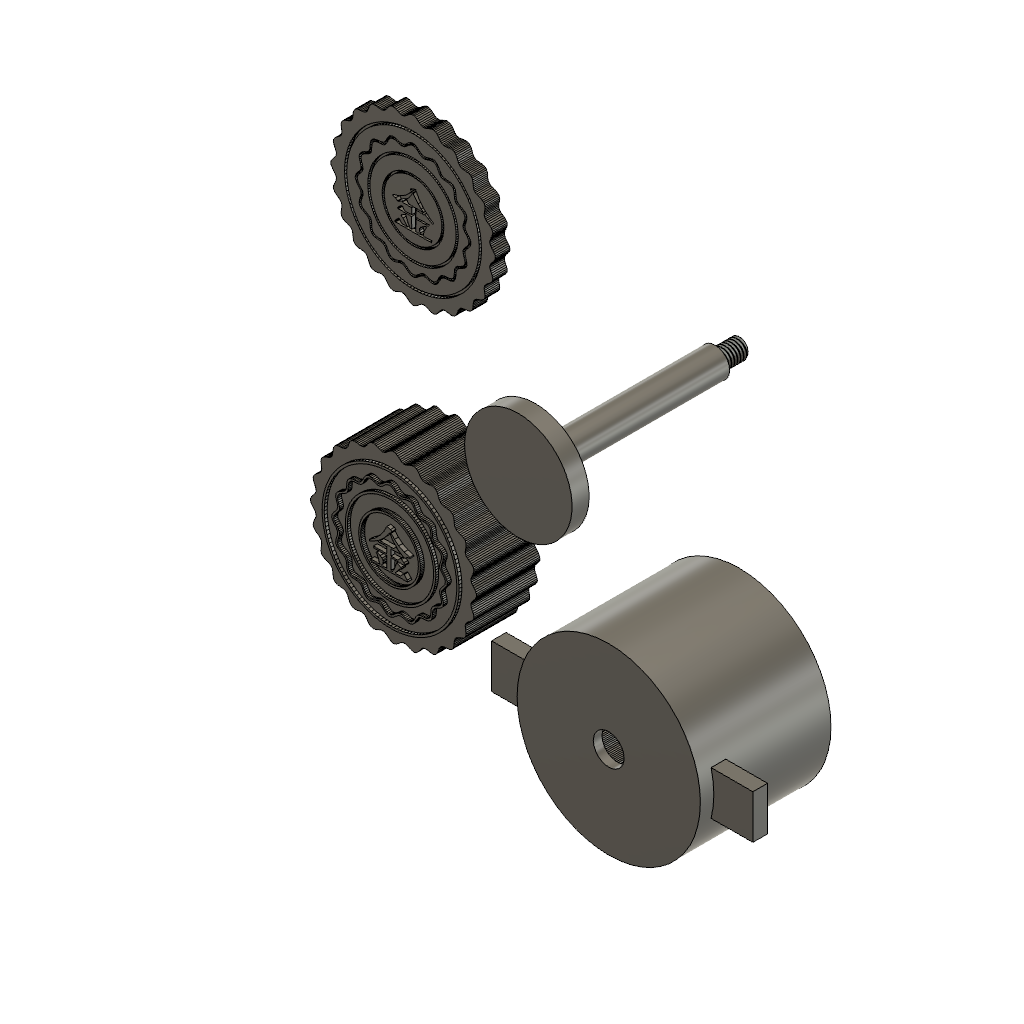
Mooncake-金-68mm-月饼与模具 (Autodesk Fusion 360 design; units mm, degrees)
part number: 2026-09-19-11-01-06-843
part number: 2026-09-19-11-01-06-994
part number: 2026-09-19-11-01-14-497
part number: 2026-09-19-11-01-14-514
part number: 2026-09-19-11-01-14-529
Autodesk Fusion 360 part; units mm, degrees
(part 1 of 5)
sketch "草图1" plane through (0, 0, 0) normal (0, 0, 1) x (1, 0, 0) in component "01_月饼_金_68mm"
  line L0 (34, 0) -> (33.9193, 0.5551)
  line L1 (33.9193, 0.5551) -> (33.6891, 1.1029)
  line L2 (33.6891, 1.1029) -> (33.3425, 1.638)
  line L3 (33.3425, 1.638) -> (32.9293, 2.1583)
  line L4 (32.9293, 2.1583) -> (32.5082, 2.6655)
  line L5 (32.5082, 2.6655) -> (32.1374, 3.1653)
  line L6 (32.1374, 3.1653) -> (31.866, 3.6659)
  line L7 (31.866, 3.6659) -> (31.7262, 4.1768)
  line L8 (31.7262, 4.1768) -> (31.7289, 4.7065)
  line L9 (31.7289, 4.7065) -> (31.8616, 5.2604)
  line L10 (31.8616, 5.2604) -> (32.0904, 5.839)
  line L11 (32.0904, 5.839) -> (32.3659, 6.438)
  line L12 (32.3659, 6.438) -> (32.6303, 7.0475)
  line L13 (32.6303, 7.0475) -> (32.8266, 7.6541)
  line L14 (32.8266, 7.6541) -> (32.9072, 8.2428)
  line L15 (32.9072, 8.2428) -> (32.8415, 8.7998)
  line L16 (32.8415, 8.7998) -> (32.6199, 9.3151)
  line L17 (32.6199, 9.3151) -> (32.2557, 9.7847)
  line L18 (32.2557, 9.7847) -> (31.7824, 10.2119)
  line L19 (31.7824, 10.2119) -> (31.2487, 10.6075)
  line L20 (31.2487, 10.6075) -> (30.7106, 10.9884)
  line L21 (30.7106, 10.9884) -> (30.2231, 11.3752)
  line L22 (30.2231, 11.3752) -> (29.8313, 11.7885)
  line L23 (29.8313, 11.7885) -> (29.5641, 12.2459)
  line L24 (29.5641, 12.2459) -> (29.4297, 12.7582)
  line L25 (29.4297, 12.7582) -> (29.4144, 13.3275)
  line L26 (29.4144, 13.3275) -> (29.4857, 13.9457)
  line L27 (29.4857, 13.9457) -> (29.5968, 14.5955)
  line L28 (29.5968, 14.5955) -> (29.6944, 15.2527)
  line L29 (29.6944, 15.2527) -> (29.727, 15.8894)
  line L30 (29.727, 15.8894) -> (29.6525, 16.479)
  line L31 (29.6525, 16.479) -> (29.4449, 17)
  line L32 (29.4449, 17) -> (29.0975, 17.4404)
  line L33 (29.0975, 17.4404) -> (28.6241, 17.7996)
  line L34 (28.6241, 17.7996) -> (28.0564, 18.0898)
  line L35 (28.0564, 18.0898) -> (27.4385, 18.3338)
  line L36 (27.4385, 18.3338) -> (26.8202, 18.5625)
  line L37 (26.8202, 18.5625) -> (26.2492, 18.8099)
  line L38 (26.2492, 18.8099) -> (25.7638, 19.1077)
  line L39 (25.7638, 19.1077) -> (25.3873, 19.4804)
  line L40 (25.3873, 19.4804) -> (25.1248, 19.9405)
  line L41 (25.1248, 19.9405) -> (24.9627, 20.4864)
  line L42 (24.9627, 20.4864) -> (24.8716, 21.102)
  line L43 (24.8716, 21.102) -> (24.8107, 21.7584)
  line L44 (24.8107, 21.7584) -> (24.7349, 22.4184)
  line L45 (24.7349, 22.4184) -> (24.6016, 23.0419)
  line L46 (24.6016, 23.0419) -> (24.3771, 23.5921)
  line L47 (24.3771, 23.5921) -> (24.0416, 24.0416)
  line L48 (24.0416, 24.0416) -> (23.5921, 24.3771)
  line L49 (23.5921, 24.3771) -> (23.0419, 24.6016)
  line L50 (23.0419, 24.6016) -> (22.4184, 24.7349)
  line L51 (22.4184, 24.7349) -> (21.7584, 24.8107)
  line L52 (21.7584, 24.8107) -> (21.102, 24.8716)
  line L53 (21.102, 24.8716) -> (20.4864, 24.9627)
  line L54 (20.4864, 24.9627) -> (19.9405, 25.1248)
  line L55 (19.9405, 25.1248) -> (19.4804, 25.3873)
  line L56 (19.4804, 25.3873) -> (19.1077, 25.7638)
  line L57 (19.1077, 25.7638) -> (18.8099, 26.2492)
  line L58 (18.8099, 26.2492) -> (18.5625, 26.8202)
  line L59 (18.5625, 26.8202) -> (18.3338, 27.4385)
  line L60 (18.3338, 27.4385) -> (18.0898, 28.0564)
  line L61 (18.0898, 28.0564) -> (17.7996, 28.6241)
  line L62 (17.7996, 28.6241) -> (17.4404, 29.0975)
  line L63 (17.4404, 29.0975) -> (17, 29.4449)
  line L64 (17, 29.4449) -> (16.479, 29.6525)
  line L65 (16.479, 29.6525) -> (15.8894, 29.727)
  line L66 (15.8894, 29.727) -> (15.2527, 29.6944)
  line L67 (15.2527, 29.6944) -> (14.5955, 29.5968)
  line L68 (14.5955, 29.5968) -> (13.9457, 29.4857)
  line L69 (13.9457, 29.4857) -> (13.3275, 29.4144)
  line L70 (13.3275, 29.4144) -> (12.7582, 29.4297)
  line L71 (12.7582, 29.4297) -> (12.2459, 29.5641)
  line L72 (12.2459, 29.5641) -> (11.7885, 29.8313)
  line L73 (11.7885, 29.8313) -> (11.3752, 30.2231)
  line L74 (11.3752, 30.2231) -> (10.9884, 30.7106)
  line L75 (10.9884, 30.7106) -> (10.6075, 31.2487)
  line L76 (10.6075, 31.2487) -> (10.2119, 31.7824)
  line L77 (10.2119, 31.7824) -> (9.7847, 32.2557)
  line L78 (9.7847, 32.2557) -> (9.3151, 32.6199)
  line L79 (9.3151, 32.6199) -> (8.7998, 32.8415)
  line L80 (8.7998, 32.8415) -> (8.2428, 32.9072)
  line L81 (8.2428, 32.9072) -> (7.6541, 32.8266)
  line L82 (7.6541, 32.8266) -> (7.0475, 32.6303)
  line L83 (7.0475, 32.6303) -> (6.438, 32.3659)
  line L84 (6.438, 32.3659) -> (5.839, 32.0904)
  line L85 (5.839, 32.0904) -> (5.2604, 31.8616)
  line L86 (5.2604, 31.8616) -> (4.7065, 31.7289)
  line L87 (4.7065, 31.7289) -> (4.1768, 31.7262)
  line L88 (4.1768, 31.7262) -> (3.6659, 31.866)
  line L89 (3.6659, 31.866) -> (3.1653, 32.1374)
  line L90 (3.1653, 32.1374) -> (2.6655, 32.5082)
  line L91 (2.6655, 32.5082) -> (2.1583, 32.9293)
  line L92 (2.1583, 32.9293) -> (1.638, 33.3425)
  line L93 (1.638, 33.3425) -> (1.1029, 33.6891)
  line L94 (1.1029, 33.6891) -> (0.5551, 33.9193)
  line L95 (0.5551, 33.9193) -> (0, 34)
  line L96 (0, 34) -> (-0.5551, 33.9193)
  line L97 (-0.5551, 33.9193) -> (-1.1029, 33.6891)
  line L98 (-1.1029, 33.6891) -> (-1.638, 33.3425)
  line L99 (-1.638, 33.3425) -> (-2.1583, 32.9293)
  line L100 (-2.1583, 32.9293) -> (-2.6655, 32.5082)
  line L101 (-2.6655, 32.5082) -> (-3.1653, 32.1374)
  line L102 (-3.1653, 32.1374) -> (-3.6659, 31.866)
  line L103 (-3.6659, 31.866) -> (-4.1768, 31.7262)
  line L104 (-4.1768, 31.7262) -> (-4.7065, 31.7289)
  line L105 (-4.7065, 31.7289) -> (-5.2604, 31.8616)
  line L106 (-5.2604, 31.8616) -> (-5.839, 32.0904)
  line L107 (-5.839, 32.0904) -> (-6.438, 32.3659)
  line L108 (-6.438, 32.3659) -> (-7.0475, 32.6303)
  line L109 (-7.0475, 32.6303) -> (-7.6541, 32.8266)
  line L110 (-7.6541, 32.8266) -> (-8.2428, 32.9072)
  line L111 (-8.2428, 32.9072) -> (-8.7998, 32.8415)
  line L112 (-8.7998, 32.8415) -> (-9.3151, 32.6199)
  line L113 (-9.3151, 32.6199) -> (-9.7847, 32.2557)
  line L114 (-9.7847, 32.2557) -> (-10.2119, 31.7824)
  line L115 (-10.2119, 31.7824) -> (-10.6075, 31.2487)
  line L116 (-10.6075, 31.2487) -> (-10.9884, 30.7106)
  line L117 (-10.9884, 30.7106) -> (-11.3752, 30.2231)
  line L118 (-11.3752, 30.2231) -> (-11.7885, 29.8313)
  line L119 (-11.7885, 29.8313) -> (-12.2459, 29.5641)
  line L120 (-12.2459, 29.5641) -> (-12.7582, 29.4297)
  line L121 (-12.7582, 29.4297) -> (-13.3275, 29.4144)
  line L122 (-13.3275, 29.4144) -> (-13.9457, 29.4857)
  line L123 (-13.9457, 29.4857) -> (-14.5955, 29.5968)
  line L124 (-14.5955, 29.5968) -> (-15.2527, 29.6944)
  line L125 (-15.2527, 29.6944) -> (-15.8894, 29.727)
  line L126 (-15.8894, 29.727) -> (-16.479, 29.6525)
  line L127 (-16.479, 29.6525) -> (-17, 29.4449)
  line L128 (-17, 29.4449) -> (-17.4404, 29.0975)
  line L129 (-17.4404, 29.0975) -> (-17.7996, 28.6241)
  line L130 (-17.7996, 28.6241) -> (-18.0898, 28.0564)
  line L131 (-18.0898, 28.0564) -> (-18.3338, 27.4385)
  line L132 (-18.3338, 27.4385) -> (-18.5625, 26.8202)
  line L133 (-18.5625, 26.8202) -> (-18.8099, 26.2492)
  line L134 (-18.8099, 26.2492) -> (-19.1077, 25.7638)
  line L135 (-19.1077, 25.7638) -> (-19.4804, 25.3873)
  line L136 (-19.4804, 25.3873) -> (-19.9405, 25.1248)
  line L137 (-19.9405, 25.1248) -> (-20.4864, 24.9627)
  line L138 (-20.4864, 24.9627) -> (-21.102, 24.8716)
  line L139 (-21.102, 24.8716) -> (-21.7584, 24.8107)
  line L140 (-21.7584, 24.8107) -> (-22.4184, 24.7349)
  line L141 (-22.4184, 24.7349) -> (-23.0419, 24.6016)
  line L142 (-23.0419, 24.6016) -> (-23.5921, 24.3771)
  line L143 (-23.5921, 24.3771) -> (-24.0416, 24.0416)
  line L144 (-24.0416, 24.0416) -> (-24.3771, 23.5921)
  line L145 (-24.3771, 23.5921) -> (-24.6016, 23.0419)
  line L146 (-24.6016, 23.0419) -> (-24.7349, 22.4184)
  line L147 (-24.7349, 22.4184) -> (-24.8107, 21.7584)
  line L148 (-24.8107, 21.7584) -> (-24.8716, 21.102)
  line L149 (-24.8716, 21.102) -> (-24.9627, 20.4864)
  line L150 (-24.9627, 20.4864) -> (-25.1248, 19.9405)
  line L151 (-25.1248, 19.9405) -> (-25.3873, 19.4804)
  line L152 (-25.3873, 19.4804) -> (-25.7638, 19.1077)
  line L153 (-25.7638, 19.1077) -> (-26.2492, 18.8099)
  line L154 (-26.2492, 18.8099) -> (-26.8202, 18.5625)
  line L155 (-26.8202, 18.5625) -> (-27.4385, 18.3338)
  line L156 (-27.4385, 18.3338) -> (-28.0564, 18.0898)
  line L157 (-28.0564, 18.0898) -> (-28.6241, 17.7996)
  line L158 (-28.6241, 17.7996) -> (-29.0975, 17.4404)
  line L159 (-29.0975, 17.4404) -> (-29.4449, 17)
  line L160 (-29.4449, 17) -> (-29.6525, 16.479)
  line L161 (-29.6525, 16.479) -> (-29.727, 15.8894)
  line L162 (-29.727, 15.8894) -> (-29.6944, 15.2527)
  line L163 (-29.6944, 15.2527) -> (-29.5968, 14.5955)
  line L164 (-29.5968, 14.5955) -> (-29.4857, 13.9457)
  line L165 (-29.4857, 13.9457) -> (-29.4144, 13.3275)
  line L166 (-29.4144, 13.3275) -> (-29.4297, 12.7582)
  line L167 (-29.4297, 12.7582) -> (-29.5641, 12.2459)
  line L168 (-29.5641, 12.2459) -> (-29.8313, 11.7885)
  line L169 (-29.8313, 11.7885) -> (-30.2231, 11.3752)
  line L170 (-30.2231, 11.3752) -> (-30.7106, 10.9884)
  line L171 (-30.7106, 10.9884) -> (-31.2487, 10.6075)
  line L172 (-31.2487, 10.6075) -> (-31.7824, 10.2119)
  line L173 (-31.7824, 10.2119) -> (-32.2557, 9.7847)
  line L174 (-32.2557, 9.7847) -> (-32.6199, 9.3151)
  line L175 (-32.6199, 9.3151) -> (-32.8415, 8.7998)
  line L176 (-32.8415, 8.7998) -> (-32.9072, 8.2428)
  line L177 (-32.9072, 8.2428) -> (-32.8266, 7.6541)
  line L178 (-32.8266, 7.6541) -> (-32.6303, 7.0475)
  line L179 (-32.6303, 7.0475) -> (-32.3659, 6.438)
  line L180 (-32.3659, 6.438) -> (-32.0904, 5.839)
  line L181 (-32.0904, 5.839) -> (-31.8616, 5.2604)
  line L182 (-31.8616, 5.2604) -> (-31.7289, 4.7065)
  line L183 (-31.7289, 4.7065) -> (-31.7262, 4.1768)
  line L184 (-31.7262, 4.1768) -> (-31.866, 3.6659)
  line L185 (-31.866, 3.6659) -> (-32.1374, 3.1653)
  line L186 (-32.1374, 3.1653) -> (-32.5082, 2.6655)
  line L187 (-32.5082, 2.6655) -> (-32.9293, 2.1583)
  line L188 (-32.9293, 2.1583) -> (-33.3425, 1.638)
  line L189 (-33.3425, 1.638) -> (-33.6891, 1.1029)
  line L190 (-33.6891, 1.1029) -> (-33.9193, 0.5551)
  line L191 (-33.9193, 0.5551) -> (-34, 0)
  line L192 (-34, 0) -> (-33.9193, -0.5551)
  line L193 (-33.9193, -0.5551) -> (-33.6891, -1.1029)
  line L194 (-33.6891, -1.1029) -> (-33.3425, -1.638)
  line L195 (-33.3425, -1.638) -> (-32.9293, -2.1583)
  line L196 (-32.9293, -2.1583) -> (-32.5082, -2.6655)
  line L197 (-32.5082, -2.6655) -> (-32.1374, -3.1653)
  line L198 (-32.1374, -3.1653) -> (-31.866, -3.6659)
  line L199 (-31.866, -3.6659) -> (-31.7262, -4.1768)
  line L200 (-31.7262, -4.1768) -> (-31.7289, -4.7065)
  line L201 (-31.7289, -4.7065) -> (-31.8616, -5.2604)
  line L202 (-31.8616, -5.2604) -> (-32.0904, -5.839)
  line L203 (-32.0904, -5.839) -> (-32.3659, -6.438)
  line L204 (-32.3659, -6.438) -> (-32.6303, -7.0475)
  line L205 (-32.6303, -7.0475) -> (-32.8266, -7.6541)
  line L206 (-32.8266, -7.6541) -> (-32.9072, -8.2428)
  line L207 (-32.9072, -8.2428) -> (-32.8415, -8.7998)
  line L208 (-32.8415, -8.7998) -> (-32.6199, -9.3151)
  line L209 (-32.6199, -9.3151) -> (-32.2557, -9.7847)
  line L210 (-32.2557, -9.7847) -> (-31.7824, -10.2119)
  line L211 (-31.7824, -10.2119) -> (-31.2487, -10.6075)
  line L212 (-31.2487, -10.6075) -> (-30.7106, -10.9884)
  line L213 (-30.7106, -10.9884) -> (-30.2231, -11.3752)
  line L214 (-30.2231, -11.3752) -> (-29.8313, -11.7885)
  line L215 (-29.8313, -11.7885) -> (-29.5641, -12.2459)
  line L216 (-29.5641, -12.2459) -> (-29.4297, -12.7582)
  line L217 (-29.4297, -12.7582) -> (-29.4144, -13.3275)
  line L218 (-29.4144, -13.3275) -> (-29.4857, -13.9457)
  line L219 (-29.4857, -13.9457) -> (-29.5968, -14.5955)
  line L220 (-29.5968, -14.5955) -> (-29.6944, -15.2527)
  line L221 (-29.6944, -15.2527) -> (-29.727, -15.8894)
  line L222 (-29.727, -15.8894) -> (-29.6525, -16.479)
  line L223 (-29.6525, -16.479) -> (-29.4449, -17)
  line L224 (-29.4449, -17) -> (-29.0975, -17.4404)
  line L225 (-29.0975, -17.4404) -> (-28.6241, -17.7996)
  line L226 (-28.6241, -17.7996) -> (-28.0564, -18.0898)
  line L227 (-28.0564, -18.0898) -> (-27.4385, -18.3338)
  line L228 (-27.4385, -18.3338) -> (-26.8202, -18.5625)
  line L229 (-26.8202, -18.5625) -> (-26.2492, -18.8099)
  line L230 (-26.2492, -18.8099) -> (-25.7638, -19.1077)
  line L231 (-25.7638, -19.1077) -> (-25.3873, -19.4804)
  line L232 (-25.3873, -19.4804) -> (-25.1248, -19.9405)
  line L233 (-25.1248, -19.9405) -> (-24.9627, -20.4864)
  line L234 (-24.9627, -20.4864) -> (-24.8716, -21.102)
  line L235 (-24.8716, -21.102) -> (-24.8107, -21.7584)
  line L236 (-24.8107, -21.7584) -> (-24.7349, -22.4184)
  line L237 (-24.7349, -22.4184) -> (-24.6016, -23.0419)
  line L238 (-24.6016, -23.0419) -> (-24.3771, -23.5921)
  line L239 (-24.3771, -23.5921) -> (-24.0416, -24.0416)
  line L240 (-24.0416, -24.0416) -> (-23.5921, -24.3771)
  line L241 (-23.5921, -24.3771) -> (-23.0419, -24.6016)
  line L242 (-23.0419, -24.6016) -> (-22.4184, -24.7349)
  line L243 (-22.4184, -24.7349) -> (-21.7584, -24.8107)
  line L244 (-21.7584, -24.8107) -> (-21.102, -24.8716)
  line L245 (-21.102, -24.8716) -> (-20.4864, -24.9627)
  line L246 (-20.4864, -24.9627) -> (-19.9405, -25.1248)
  line L247 (-19.9405, -25.1248) -> (-19.4804, -25.3873)
  line L248 (-19.4804, -25.3873) -> (-19.1077, -25.7638)
  line L249 (-19.1077, -25.7638) -> (-18.8099, -26.2492)
  line L250 (-18.8099, -26.2492) -> (-18.5625, -26.8202)
  line L251 (-18.5625, -26.8202) -> (-18.3338, -27.4385)
  line L252 (-18.3338, -27.4385) -> (-18.0898, -28.0564)
  line L253 (-18.0898, -28.0564) -> (-17.7996, -28.6241)
  line L254 (-17.7996, -28.6241) -> (-17.4404, -29.0975)
  line L255 (-17.4404, -29.0975) -> (-17, -29.4449)
  line L256 (-17, -29.4449) -> (-16.479, -29.6525)
  line L257 (-16.479, -29.6525) -> (-15.8894, -29.727)
  line L258 (-15.8894, -29.727) -> (-15.2527, -29.6944)
  line L259 (-15.2527, -29.6944) -> (-14.5955, -29.5968)
  line L260 (-14.5955, -29.5968) -> (-13.9457, -29.4857)
  line L261 (-13.9457, -29.4857) -> (-13.3275, -29.4144)
  line L262 (-13.3275, -29.4144) -> (-12.7582, -29.4297)
  line L263 (-12.7582, -29.4297) -> (-12.2459, -29.5641)
  line L264 (-12.2459, -29.5641) -> (-11.7885, -29.8313)
  line L265 (-11.7885, -29.8313) -> (-11.3752, -30.2231)
  line L266 (-11.3752, -30.2231) -> (-10.9884, -30.7106)
  line L267 (-10.9884, -30.7106) -> (-10.6075, -31.2487)
  line L268 (-10.6075, -31.2487) -> (-10.2119, -31.7824)
  line L269 (-10.2119, -31.7824) -> (-9.7847, -32.2557)
  line L270 (-9.7847, -32.2557) -> (-9.3151, -32.6199)
  line L271 (-9.3151, -32.6199) -> (-8.7998, -32.8415)
  line L272 (-8.7998, -32.8415) -> (-8.2428, -32.9072)
  line L273 (-8.2428, -32.9072) -> (-7.6541, -32.8266)
  line L274 (-7.6541, -32.8266) -> (-7.0475, -32.6303)
  line L275 (-7.0475, -32.6303) -> (-6.438, -32.3659)
  line L276 (-6.438, -32.3659) -> (-5.839, -32.0904)
  line L277 (-5.839, -32.0904) -> (-5.2604, -31.8616)
  line L278 (-5.2604, -31.8616) -> (-4.7065, -31.7289)
  line L279 (-4.7065, -31.7289) -> (-4.1768, -31.7262)
  line L280 (-4.1768, -31.7262) -> (-3.6659, -31.866)
  line L281 (-3.6659, -31.866) -> (-3.1653, -32.1374)
  line L282 (-3.1653, -32.1374) -> (-2.6655, -32.5082)
  line L283 (-2.6655, -32.5082) -> (-2.1583, -32.9293)
  line L284 (-2.1583, -32.9293) -> (-1.638, -33.3425)
  line L285 (-1.638, -33.3425) -> (-1.1029, -33.6891)
  line L286 (-1.1029, -33.6891) -> (-0.5551, -33.9193)
  line L287 (-0.5551, -33.9193) -> (0, -34)
  line L288 (0, -34) -> (0.5551, -33.9193)
  line L289 (0.5551, -33.9193) -> (1.1029, -33.6891)
  line L290 (1.1029, -33.6891) -> (1.638, -33.3425)
  line L291 (1.638, -33.3425) -> (2.1583, -32.9293)
  line L292 (2.1583, -32.9293) -> (2.6655, -32.5082)
  line L293 (2.6655, -32.5082) -> (3.1653, -32.1374)
  line L294 (3.1653, -32.1374) -> (3.6659, -31.866)
  line L295 (3.6659, -31.866) -> (4.1768, -31.7262)
  line L296 (4.1768, -31.7262) -> (4.7065, -31.7289)
  line L297 (4.7065, -31.7289) -> (5.2604, -31.8616)
  line L298 (5.2604, -31.8616) -> (5.839, -32.0904)
  line L299 (5.839, -32.0904) -> (6.438, -32.3659)
  line L300 (6.438, -32.3659) -> (7.0475, -32.6303)
  line L301 (7.0475, -32.6303) -> (7.6541, -32.8266)
  line L302 (7.6541, -32.8266) -> (8.2428, -32.9072)
  line L303 (8.2428, -32.9072) -> (8.7998, -32.8415)
  line L304 (8.7998, -32.8415) -> (9.3151, -32.6199)
  line L305 (9.3151, -32.6199) -> (9.7847, -32.2557)
  line L306 (9.7847, -32.2557) -> (10.2119, -31.7824)
  line L307 (10.2119, -31.7824) -> (10.6075, -31.2487)
  line L308 (10.6075, -31.2487) -> (10.9884, -30.7106)
  line L309 (10.9884, -30.7106) -> (11.3752, -30.2231)
  line L310 (11.3752, -30.2231) -> (11.7885, -29.8313)
  line L311 (11.7885, -29.8313) -> (12.2459, -29.5641)
  line L312 (12.2459, -29.5641) -> (12.7582, -29.4297)
  line L313 (12.7582, -29.4297) -> (13.3275, -29.4144)
  line L314 (13.3275, -29.4144) -> (13.9457, -29.4857)
  line L315 (13.9457, -29.4857) -> (14.5955, -29.5968)
  line L316 (14.5955, -29.5968) -> (15.2527, -29.6944)
  line L317 (15.2527, -29.6944) -> (15.8894, -29.727)
  line L318 (15.8894, -29.727) -> (16.479, -29.6525)
  line L319 (16.479, -29.6525) -> (17, -29.4449)
  line L320 (17, -29.4449) -> (17.4404, -29.0975)
  line L321 (17.4404, -29.0975) -> (17.7996, -28.6241)
  line L322 (17.7996, -28.6241) -> (18.0898, -28.0564)
  line L323 (18.0898, -28.0564) -> (18.3338, -27.4385)
  line L324 (18.3338, -27.4385) -> (18.5625, -26.8202)
  line L325 (18.5625, -26.8202) -> (18.8099, -26.2492)
  line L326 (18.8099, -26.2492) -> (19.1077, -25.7638)
  line L327 (19.1077, -25.7638) -> (19.4804, -25.3873)
  line L328 (19.4804, -25.3873) -> (19.9405, -25.1248)
  line L329 (19.9405, -25.1248) -> (20.4864, -24.9627)
  line L330 (20.4864, -24.9627) -> (21.102, -24.8716)
  line L331 (21.102, -24.8716) -> (21.7584, -24.8107)
  line L332 (21.7584, -24.8107) -> (22.4184, -24.7349)
  line L333 (22.4184, -24.7349) -> (23.0419, -24.6016)
  line L334 (23.0419, -24.6016) -> (23.5921, -24.3771)
  line L335 (23.5921, -24.3771) -> (24.0416, -24.0416)
  line L336 (24.0416, -24.0416) -> (24.3771, -23.5921)
  line L337 (24.3771, -23.5921) -> (24.6016, -23.0419)
  line L338 (24.6016, -23.0419) -> (24.7349, -22.4184)
  line L339 (24.7349, -22.4184) -> (24.8107, -21.7584)
  line L340 (24.8107, -21.7584) -> (24.8716, -21.102)
  line L341 (24.8716, -21.102) -> (24.9627, -20.4864)
  line L342 (24.9627, -20.4864) -> (25.1248, -19.9405)
  line L343 (25.1248, -19.9405) -> (25.3873, -19.4804)
  line L344 (25.3873, -19.4804) -> (25.7638, -19.1077)
  line L345 (25.7638, -19.1077) -> (26.2492, -18.8099)
  line L346 (26.2492, -18.8099) -> (26.8202, -18.5625)
  line L347 (26.8202, -18.5625) -> (27.4385, -18.3338)
  line L348 (27.4385, -18.3338) -> (28.0564, -18.0898)
  line L349 (28.0564, -18.0898) -> (28.6241, -17.7996)
  line L350 (28.6241, -17.7996) -> (29.0975, -17.4404)
  line L351 (29.0975, -17.4404) -> (29.4449, -17)
  line L352 (29.4449, -17) -> (29.6525, -16.479)
  line L353 (29.6525, -16.479) -> (29.727, -15.8894)
  line L354 (29.727, -15.8894) -> (29.6944, -15.2527)
  line L355 (29.6944, -15.2527) -> (29.5968, -14.5955)
  line L356 (29.5968, -14.5955) -> (29.4857, -13.9457)
  line L357 (29.4857, -13.9457) -> (29.4144, -13.3275)
  line L358 (29.4144, -13.3275) -> (29.4297, -12.7582)
  line L359 (29.4297, -12.7582) -> (29.5641, -12.2459)
  line L360 (29.5641, -12.2459) -> (29.8313, -11.7885)
  line L361 (29.8313, -11.7885) -> (30.2231, -11.3752)
  line L362 (30.2231, -11.3752) -> (30.7106, -10.9884)
  line L363 (30.7106, -10.9884) -> (31.2487, -10.6075)
  line L364 (31.2487, -10.6075) -> (31.7824, -10.2119)
  line L365 (31.7824, -10.2119) -> (32.2557, -9.7847)
  line L366 (32.2557, -9.7847) -> (32.6199, -9.3151)
  line L367 (32.6199, -9.3151) -> (32.8415, -8.7998)
  line L368 (32.8415, -8.7998) -> (32.9072, -8.2428)
  line L369 (32.9072, -8.2428) -> (32.8266, -7.6541)
  line L370 (32.8266, -7.6541) -> (32.6303, -7.0475)
  line L371 (32.6303, -7.0475) -> (32.3659, -6.438)
  line L372 (32.3659, -6.438) -> (32.0904, -5.839)
  line L373 (32.0904, -5.839) -> (31.8616, -5.2604)
  line L374 (31.8616, -5.2604) -> (31.7289, -4.7065)
  line L375 (31.7289, -4.7065) -> (31.7262, -4.1768)
  line L376 (31.7262, -4.1768) -> (31.866, -3.6659)
  line L377 (31.866, -3.6659) -> (32.1374, -3.1653)
  line L378 (32.1374, -3.1653) -> (32.5082, -2.6655)
  line L379 (32.5082, -2.6655) -> (32.9293, -2.1583)
  line L380 (32.9293, -2.1583) -> (33.3425, -1.638)
  line L381 (33.3425, -1.638) -> (33.6891, -1.1029)
  line L382 (33.6891, -1.1029) -> (33.9193, -0.5551)
  line L383 (33.9193, -0.5551) -> (34, 0)
extrude "月饼厚度" add sketch "草图1" along normal blind 26 makes body 1 in component "01_月饼_金_68mm"
ref_plane "工作平面1" through (0, 0, 25.97) normal (0, 0, 1) x (1, 0, 0) in component "01_月饼_金_68mm"
sketch "草图2" plane through (0, 0, 25.97) normal (0, 0, 1) x (1, 0, 0) in component "01_月饼_金_68mm"
  line L0 (28, 0) -> (27.9663, 1.3739)
  line L1 (27.9663, 1.3739) -> (27.8652, 2.7445)
  line L2 (27.8652, 2.7445) -> (27.6969, 4.1085)
  line L3 (27.6969, 4.1085) -> (27.462, 5.4625)
  line L4 (27.462, 5.4625) -> (27.1609, 6.8034)
  line L5 (27.1609, 6.8034) -> (26.7943, 8.128)
  line L6 (26.7943, 8.128) -> (26.3632, 9.4329)
  line L7 (26.3632, 9.4329) -> (25.8686, 10.7151)
  line L8 (25.8686, 10.7151) -> (25.3117, 11.9715)
  line L9 (25.3117, 11.9715) -> (24.6938, 13.1991)
  line L10 (24.6938, 13.1991) -> (24.0164, 14.3949)
  line L11 (24.0164, 14.3949) -> (23.2811, 15.556)
  line L12 (23.2811, 15.556) -> (22.4898, 16.6796)
  line L13 (22.4898, 16.6796) -> (21.6443, 17.763)
  line L14 (21.6443, 17.763) -> (20.7466, 18.8037)
  line L15 (20.7466, 18.8037) -> (19.799, 19.799)
  line L16 (19.799, 19.799) -> (18.8037, 20.7466)
  line L17 (18.8037, 20.7466) -> (17.763, 21.6443)
  line L18 (17.763, 21.6443) -> (16.6796, 22.4898)
  line L19 (16.6796, 22.4898) -> (15.556, 23.2811)
  line L20 (15.556, 23.2811) -> (14.3949, 24.0164)
  line L21 (14.3949, 24.0164) -> (13.1991, 24.6938)
  line L22 (13.1991, 24.6938) -> (11.9715, 25.3117)
  line L23 (11.9715, 25.3117) -> (10.7151, 25.8686)
  line L24 (10.7151, 25.8686) -> (9.4329, 26.3632)
  line L25 (9.4329, 26.3632) -> (8.128, 26.7943)
  line L26 (8.128, 26.7943) -> (6.8034, 27.1609)
  line L27 (6.8034, 27.1609) -> (5.4625, 27.462)
  line L28 (5.4625, 27.462) -> (4.1085, 27.6969)
  line L29 (4.1085, 27.6969) -> (2.7445, 27.8652)
  line L30 (2.7445, 27.8652) -> (1.3739, 27.9663)
  line L31 (1.3739, 27.9663) -> (0, 28)
  line L32 (0, 28) -> (-1.3739, 27.9663)
  line L33 (-1.3739, 27.9663) -> (-2.7445, 27.8652)
  line L34 (-2.7445, 27.8652) -> (-4.1085, 27.6969)
  line L35 (-4.1085, 27.6969) -> (-5.4625, 27.462)
  line L36 (-5.4625, 27.462) -> (-6.8034, 27.1609)
  line L37 (-6.8034, 27.1609) -> (-8.128, 26.7943)
  line L38 (-8.128, 26.7943) -> (-9.4329, 26.3632)
  line L39 (-9.4329, 26.3632) -> (-10.7151, 25.8686)
  line L40 (-10.7151, 25.8686) -> (-11.9715, 25.3117)
  line L41 (-11.9715, 25.3117) -> (-13.1991, 24.6938)
  line L42 (-13.1991, 24.6938) -> (-14.3949, 24.0164)
  line L43 (-14.3949, 24.0164) -> (-15.556, 23.2811)
  line L44 (-15.556, 23.2811) -> (-16.6796, 22.4898)
  line L45 (-16.6796, 22.4898) -> (-17.763, 21.6443)
  line L46 (-17.763, 21.6443) -> (-18.8037, 20.7466)
  line L47 (-18.8037, 20.7466) -> (-19.799, 19.799)
  line L48 (-19.799, 19.799) -> (-20.7466, 18.8037)
  line L49 (-20.7466, 18.8037) -> (-21.6443, 17.763)
  line L50 (-21.6443, 17.763) -> (-22.4898, 16.6796)
  line L51 (-22.4898, 16.6796) -> (-23.2811, 15.556)
  line L52 (-23.2811, 15.556) -> (-24.0164, 14.3949)
  line L53 (-24.0164, 14.3949) -> (-24.6938, 13.1991)
  line L54 (-24.6938, 13.1991) -> (-25.3117, 11.9715)
  line L55 (-25.3117, 11.9715) -> (-25.8686, 10.7151)
  line L56 (-25.8686, 10.7151) -> (-26.3632, 9.4329)
  line L57 (-26.3632, 9.4329) -> (-26.7943, 8.128)
  line L58 (-26.7943, 8.128) -> (-27.1609, 6.8034)
  line L59 (-27.1609, 6.8034) -> (-27.462, 5.4625)
  line L60 (-27.462, 5.4625) -> (-27.6969, 4.1085)
  line L61 (-27.6969, 4.1085) -> (-27.8652, 2.7445)
  line L62 (-27.8652, 2.7445) -> (-27.9663, 1.3739)
  line L63 (-27.9663, 1.3739) -> (-28, 0)
  line L64 (-28, 0) -> (-27.9663, -1.3739)
  line L65 (-27.9663, -1.3739) -> (-27.8652, -2.7445)
  line L66 (-27.8652, -2.7445) -> (-27.6969, -4.1085)
  line L67 (-27.6969, -4.1085) -> (-27.462, -5.4625)
  line L68 (-27.462, -5.4625) -> (-27.1609, -6.8034)
  line L69 (-27.1609, -6.8034) -> (-26.7943, -8.128)
  line L70 (-26.7943, -8.128) -> (-26.3632, -9.4329)
  line L71 (-26.3632, -9.4329) -> (-25.8686, -10.7151)
  line L72 (-25.8686, -10.7151) -> (-25.3117, -11.9715)
  line L73 (-25.3117, -11.9715) -> (-24.6938, -13.1991)
  line L74 (-24.6938, -13.1991) -> (-24.0164, -14.3949)
  line L75 (-24.0164, -14.3949) -> (-23.2811, -15.556)
  line L76 (-23.2811, -15.556) -> (-22.4898, -16.6796)
  line L77 (-22.4898, -16.6796) -> (-21.6443, -17.763)
  line L78 (-21.6443, -17.763) -> (-20.7466, -18.8037)
  line L79 (-20.7466, -18.8037) -> (-19.799, -19.799)
  line L80 (-19.799, -19.799) -> (-18.8037, -20.7466)
  line L81 (-18.8037, -20.7466) -> (-17.763, -21.6443)
  line L82 (-17.763, -21.6443) -> (-16.6796, -22.4898)
  line L83 (-16.6796, -22.4898) -> (-15.556, -23.2811)
  line L84 (-15.556, -23.2811) -> (-14.3949, -24.0164)
  line L85 (-14.3949, -24.0164) -> (-13.1991, -24.6938)
  line L86 (-13.1991, -24.6938) -> (-11.9715, -25.3117)
  line L87 (-11.9715, -25.3117) -> (-10.7151, -25.8686)
  line L88 (-10.7151, -25.8686) -> (-9.4329, -26.3632)
  line L89 (-9.4329, -26.3632) -> (-8.128, -26.7943)
  line L90 (-8.128, -26.7943) -> (-6.8034, -27.1609)
  line L91 (-6.8034, -27.1609) -> (-5.4625, -27.462)
  line L92 (-5.4625, -27.462) -> (-4.1085, -27.6969)
  line L93 (-4.1085, -27.6969) -> (-2.7445, -27.8652)
  line L94 (-2.7445, -27.8652) -> (-1.3739, -27.9663)
  line L95 (-1.3739, -27.9663) -> (0, -28)
  line L96 (0, -28) -> (1.3739, -27.9663)
  line L97 (1.3739, -27.9663) -> (2.7445, -27.8652)
  line L98 (2.7445, -27.8652) -> (4.1085, -27.6969)
  line L99 (4.1085, -27.6969) -> (5.4625, -27.462)
  line L100 (5.4625, -27.462) -> (6.8034, -27.1609)
  line L101 (6.8034, -27.1609) -> (8.128, -26.7943)
  line L102 (8.128, -26.7943) -> (9.4329, -26.3632)
  line L103 (9.4329, -26.3632) -> (10.7151, -25.8686)
  line L104 (10.7151, -25.8686) -> (11.9715, -25.3117)
  line L105 (11.9715, -25.3117) -> (13.1991, -24.6938)
  line L106 (13.1991, -24.6938) -> (14.3949, -24.0164)
  line L107 (14.3949, -24.0164) -> (15.556, -23.2811)
  line L108 (15.556, -23.2811) -> (16.6796, -22.4898)
  line L109 (16.6796, -22.4898) -> (17.763, -21.6443)
  line L110 (17.763, -21.6443) -> (18.8037, -20.7466)
  line L111 (18.8037, -20.7466) -> (19.799, -19.799)
  line L112 (19.799, -19.799) -> (20.7466, -18.8037)
  line L113 (20.7466, -18.8037) -> (21.6443, -17.763)
  line L114 (21.6443, -17.763) -> (22.4898, -16.6796)
  line L115 (22.4898, -16.6796) -> (23.2811, -15.556)
  line L116 (23.2811, -15.556) -> (24.0164, -14.3949)
  line L117 (24.0164, -14.3949) -> (24.6938, -13.1991)
  line L118 (24.6938, -13.1991) -> (25.3117, -11.9715)
  line L119 (25.3117, -11.9715) -> (25.8686, -10.7151)
  line L120 (25.8686, -10.7151) -> (26.3632, -9.4329)
  line L121 (26.3632, -9.4329) -> (26.7943, -8.128)
  line L122 (26.7943, -8.128) -> (27.1609, -6.8034)
  line L123 (27.1609, -6.8034) -> (27.462, -5.4625)
  line L124 (27.462, -5.4625) -> (27.6969, -4.1085)
  line L125 (27.6969, -4.1085) -> (27.8652, -2.7445)
  line L126 (27.8652, -2.7445) -> (27.9663, -1.3739)
  line L127 (27.9663, -1.3739) -> (28, 0)
  line L128 (27.0674, -1.3297) -> (26.9695, -2.6563)
  line L129 (26.9695, -2.6563) -> (26.8067, -3.9764)
  line L130 (26.8067, -3.9764) -> (26.5793, -5.2869)
  line L131 (26.5793, -5.2869) -> (26.2878, -6.5848)
  line L132 (26.2878, -6.5848) -> (25.9331, -7.8667)
  line L133 (25.9331, -7.8667) -> (25.5158, -9.1297)
  line L134 (25.5158, -9.1297) -> (25.0371, -10.3707)
  line L135 (25.0371, -10.3707) -> (24.4981, -11.5867)
  line L136 (24.4981, -11.5867) -> (23.9001, -12.7749)
  line L137 (23.9001, -12.7749) -> (23.2444, -13.9322)
  line L138 (23.2444, -13.9322) -> (22.5328, -15.056)
  line L139 (22.5328, -15.056) -> (21.7669, -16.1435)
  line L140 (21.7669, -16.1435) -> (20.9486, -17.1921)
  line L141 (20.9486, -17.1921) -> (20.0798, -18.1992)
  line L142 (20.0798, -18.1992) -> (19.1626, -19.1626)
  line L143 (19.1626, -19.1626) -> (18.1992, -20.0798)
  line L144 (18.1992, -20.0798) -> (17.1921, -20.9486)
  line L145 (17.1921, -20.9486) -> (16.1435, -21.7669)
  line L146 (16.1435, -21.7669) -> (15.056, -22.5328)
  line L147 (15.056, -22.5328) -> (13.9322, -23.2444)
  line L148 (13.9322, -23.2444) -> (12.7749, -23.9001)
  line L149 (12.7749, -23.9001) -> (11.5867, -24.4981)
  line L150 (11.5867, -24.4981) -> (10.3707, -25.0371)
  line L151 (10.3707, -25.0371) -> (9.1297, -25.5158)
  line L152 (9.1297, -25.5158) -> (7.8667, -25.9331)
  line L153 (7.8667, -25.9331) -> (6.5848, -26.2878)
  line L154 (6.5848, -26.2878) -> (5.2869, -26.5793)
  line L155 (5.2869, -26.5793) -> (3.9764, -26.8067)
  line L156 (3.9764, -26.8067) -> (2.6563, -26.9695)
  line L157 (2.6563, -26.9695) -> (1.3297, -27.0674)
  line L158 (1.3297, -27.0674) -> (0, -27.1)
  line L159 (0, -27.1) -> (-1.3297, -27.0674)
  line L160 (-1.3297, -27.0674) -> (-2.6563, -26.9695)
  line L161 (-2.6563, -26.9695) -> (-3.9764, -26.8067)
  line L162 (-3.9764, -26.8067) -> (-5.2869, -26.5793)
  line L163 (-5.2869, -26.5793) -> (-6.5848, -26.2878)
  line L164 (-6.5848, -26.2878) -> (-7.8667, -25.9331)
  line L165 (-7.8667, -25.9331) -> (-9.1297, -25.5158)
  line L166 (-9.1297, -25.5158) -> (-10.3707, -25.0371)
  line L167 (-10.3707, -25.0371) -> (-11.5867, -24.4981)
  line L168 (-11.5867, -24.4981) -> (-12.7749, -23.9001)
  line L169 (-12.7749, -23.9001) -> (-13.9322, -23.2444)
  line L170 (-13.9322, -23.2444) -> (-15.056, -22.5328)
  line L171 (-15.056, -22.5328) -> (-16.1435, -21.7669)
  line L172 (-16.1435, -21.7669) -> (-17.1921, -20.9486)
  line L173 (-17.1921, -20.9486) -> (-18.1992, -20.0798)
  line L174 (-18.1992, -20.0798) -> (-19.1626, -19.1626)
  line L175 (-19.1626, -19.1626) -> (-20.0798, -18.1992)
  line L176 (-20.0798, -18.1992) -> (-20.9486, -17.1921)
  line L177 (-20.9486, -17.1921) -> (-21.7669, -16.1435)
  line L178 (-21.7669, -16.1435) -> (-22.5328, -15.056)
  line L179 (-22.5328, -15.056) -> (-23.2444, -13.9322)
  line L180 (-23.2444, -13.9322) -> (-23.9001, -12.7749)
  line L181 (-23.9001, -12.7749) -> (-24.4981, -11.5867)
  line L182 (-24.4981, -11.5867) -> (-25.0371, -10.3707)
  line L183 (-25.0371, -10.3707) -> (-25.5158, -9.1297)
  line L184 (-25.5158, -9.1297) -> (-25.9331, -7.8667)
  line L185 (-25.9331, -7.8667) -> (-26.2878, -6.5848)
  line L186 (-26.2878, -6.5848) -> (-26.5793, -5.2869)
  line L187 (-26.5793, -5.2869) -> (-26.8067, -3.9764)
  line L188 (-26.8067, -3.9764) -> (-26.9695, -2.6563)
  line L189 (-26.9695, -2.6563) -> (-27.0674, -1.3297)
  line L190 (-27.0674, -1.3297) -> (-27.1, 0)
  line L191 (-27.1, 0) -> (-27.0674, 1.3297)
  line L192 (-27.0674, 1.3297) -> (-26.9695, 2.6563)
  line L193 (-26.9695, 2.6563) -> (-26.8067, 3.9764)
  line L194 (-26.8067, 3.9764) -> (-26.5793, 5.2869)
  line L195 (-26.5793, 5.2869) -> (-26.2878, 6.5848)
  line L196 (-26.2878, 6.5848) -> (-25.9331, 7.8667)
  line L197 (-25.9331, 7.8667) -> (-25.5158, 9.1297)
  line L198 (-25.5158, 9.1297) -> (-25.0371, 10.3707)
  line L199 (-25.0371, 10.3707) -> (-24.4981, 11.5867)
  line L200 (-24.4981, 11.5867) -> (-23.9001, 12.7749)
  line L201 (-23.9001, 12.7749) -> (-23.2444, 13.9322)
  line L202 (-23.2444, 13.9322) -> (-22.5328, 15.056)
  line L203 (-22.5328, 15.056) -> (-21.7669, 16.1435)
  line L204 (-21.7669, 16.1435) -> (-20.9486, 17.1921)
  line L205 (-20.9486, 17.1921) -> (-20.0798, 18.1992)
  line L206 (-20.0798, 18.1992) -> (-19.1626, 19.1626)
  line L207 (-19.1626, 19.1626) -> (-18.1992, 20.0798)
  line L208 (-18.1992, 20.0798) -> (-17.1921, 20.9486)
  line L209 (-17.1921, 20.9486) -> (-16.1435, 21.7669)
  line L210 (-16.1435, 21.7669) -> (-15.056, 22.5328)
  line L211 (-15.056, 22.5328) -> (-13.9322, 23.2444)
  line L212 (-13.9322, 23.2444) -> (-12.7749, 23.9001)
  line L213 (-12.7749, 23.9001) -> (-11.5867, 24.4981)
  line L214 (-11.5867, 24.4981) -> (-10.3707, 25.0371)
  line L215 (-10.3707, 25.0371) -> (-9.1297, 25.5158)
  line L216 (-9.1297, 25.5158) -> (-7.8667, 25.9331)
  line L217 (-7.8667, 25.9331) -> (-6.5848, 26.2878)
  line L218 (-6.5848, 26.2878) -> (-5.2869, 26.5793)
  line L219 (-5.2869, 26.5793) -> (-3.9764, 26.8067)
  line L220 (-3.9764, 26.8067) -> (-2.6563, 26.9695)
  line L221 (-2.6563, 26.9695) -> (-1.3297, 27.0674)
  line L222 (-1.3297, 27.0674) -> (0, 27.1)
  line L223 (0, 27.1) -> (1.3297, 27.0674)
  line L224 (1.3297, 27.0674) -> (2.6563, 26.9695)
  line L225 (2.6563, 26.9695) -> (3.9764, 26.8067)
  line L226 (3.9764, 26.8067) -> (5.2869, 26.5793)
  line L227 (5.2869, 26.5793) -> (6.5848, 26.2878)
  line L228 (6.5848, 26.2878) -> (7.8667, 25.9331)
  line L229 (7.8667, 25.9331) -> (9.1297, 25.5158)
  line L230 (9.1297, 25.5158) -> (10.3707, 25.0371)
  line L231 (10.3707, 25.0371) -> (11.5867, 24.4981)
  line L232 (11.5867, 24.4981) -> (12.7749, 23.9001)
  line L233 (12.7749, 23.9001) -> (13.9322, 23.2444)
  line L234 (13.9322, 23.2444) -> (15.056, 22.5328)
  line L235 (15.056, 22.5328) -> (16.1435, 21.7669)
  line L236 (16.1435, 21.7669) -> (17.1921, 20.9486)
  line L237 (17.1921, 20.9486) -> (18.1992, 20.0798)
  line L238 (18.1992, 20.0798) -> (19.1626, 19.1626)
  line L239 (19.1626, 19.1626) -> (20.0798, 18.1992)
  line L240 (20.0798, 18.1992) -> (20.9486, 17.1921)
  line L241 (20.9486, 17.1921) -> (21.7669, 16.1435)
  line L242 (21.7669, 16.1435) -> (22.5328, 15.056)
  line L243 (22.5328, 15.056) -> (23.2444, 13.9322)
  line L244 (23.2444, 13.9322) -> (23.9001, 12.7749)
  line L245 (23.9001, 12.7749) -> (24.4981, 11.5867)
  line L246 (24.4981, 11.5867) -> (25.0371, 10.3707)
  line L247 (25.0371, 10.3707) -> (25.5158, 9.1297)
  line L248 (25.5158, 9.1297) -> (25.9331, 7.8667)
  line L249 (25.9331, 7.8667) -> (26.2878, 6.5848)
  line L250 (26.2878, 6.5848) -> (26.5793, 5.2869)
  line L251 (26.5793, 5.2869) -> (26.8067, 3.9764)
  line L252 (26.8067, 3.9764) -> (26.9695, 2.6563)
  line L253 (26.9695, 2.6563) -> (27.0674, 1.3297)
  line L254 (27.0674, 1.3297) -> (27.1, 0)
  line L255 (27.1, 0) -> (27.0674, -1.3297)
extrude "外圈_001 (1)" add sketch "草图2" along normal blind 1.23 bodies 1 in component "01_月饼_金_68mm"
sketch "草图3" plane through (0, 0, 25.97) normal (0, 0, 1) x (1, 0, 0) in component "01_月饼_金_68mm"
  line L0 (18.48, 0) -> (18.4577, 0.9068)
  line L1 (18.4577, 0.9068) -> (18.391, 1.8114)
  line L2 (18.391, 1.8114) -> (18.28, 2.7116)
  line L3 (18.28, 2.7116) -> (18.1249, 3.6053)
  line L4 (18.1249, 3.6053) -> (17.9262, 4.4903)
  line L5 (17.9262, 4.4903) -> (17.6843, 5.3645)
  line L6 (17.6843, 5.3645) -> (17.3997, 6.2257)
  line L7 (17.3997, 6.2257) -> (17.0733, 7.072)
  line L8 (17.0733, 7.072) -> (16.7057, 7.9012)
  line L9 (16.7057, 7.9012) -> (16.2979, 8.7114)
  line L10 (16.2979, 8.7114) -> (15.8508, 9.5006)
  line L11 (15.8508, 9.5006) -> (15.3656, 10.2669)
  line L12 (15.3656, 10.2669) -> (14.8433, 11.0085)
  line L13 (14.8433, 11.0085) -> (14.2852, 11.7236)
  line L14 (14.2852, 11.7236) -> (13.6928, 12.4104)
  line L15 (13.6928, 12.4104) -> (13.0673, 13.0673)
  line L16 (13.0673, 13.0673) -> (12.4104, 13.6928)
  line L17 (12.4104, 13.6928) -> (11.7236, 14.2852)
  line L18 (11.7236, 14.2852) -> (11.0085, 14.8433)
  line L19 (11.0085, 14.8433) -> (10.2669, 15.3656)
  line L20 (10.2669, 15.3656) -> (9.5006, 15.8508)
  line L21 (9.5006, 15.8508) -> (8.7114, 16.2979)
  line L22 (8.7114, 16.2979) -> (7.9012, 16.7057)
  line L23 (7.9012, 16.7057) -> (7.072, 17.0733)
  line L24 (7.072, 17.0733) -> (6.2257, 17.3997)
  line L25 (6.2257, 17.3997) -> (5.3645, 17.6843)
  line L26 (5.3645, 17.6843) -> (4.4903, 17.9262)
  line L27 (4.4903, 17.9262) -> (3.6053, 18.1249)
  line L28 (3.6053, 18.1249) -> (2.7116, 18.28)
  line L29 (2.7116, 18.28) -> (1.8114, 18.391)
  line L30 (1.8114, 18.391) -> (0.9068, 18.4577)
  line L31 (0.9068, 18.4577) -> (0, 18.48)
  line L32 (0, 18.48) -> (-0.9068, 18.4577)
  line L33 (-0.9068, 18.4577) -> (-1.8114, 18.391)
  line L34 (-1.8114, 18.391) -> (-2.7116, 18.28)
  line L35 (-2.7116, 18.28) -> (-3.6053, 18.1249)
  line L36 (-3.6053, 18.1249) -> (-4.4903, 17.9262)
  line L37 (-4.4903, 17.9262) -> (-5.3645, 17.6843)
  line L38 (-5.3645, 17.6843) -> (-6.2257, 17.3997)
  line L39 (-6.2257, 17.3997) -> (-7.072, 17.0733)
  line L40 (-7.072, 17.0733) -> (-7.9012, 16.7057)
  line L41 (-7.9012, 16.7057) -> (-8.7114, 16.2979)
  line L42 (-8.7114, 16.2979) -> (-9.5006, 15.8508)
  line L43 (-9.5006, 15.8508) -> (-10.2669, 15.3656)
  line L44 (-10.2669, 15.3656) -> (-11.0085, 14.8433)
  line L45 (-11.0085, 14.8433) -> (-11.7236, 14.2852)
  line L46 (-11.7236, 14.2852) -> (-12.4104, 13.6928)
  line L47 (-12.4104, 13.6928) -> (-13.0673, 13.0673)
  line L48 (-13.0673, 13.0673) -> (-13.6928, 12.4104)
  line L49 (-13.6928, 12.4104) -> (-14.2852, 11.7236)
  line L50 (-14.2852, 11.7236) -> (-14.8433, 11.0085)
  line L51 (-14.8433, 11.0085) -> (-15.3656, 10.2669)
  line L52 (-15.3656, 10.2669) -> (-15.8508, 9.5006)
  line L53 (-15.8508, 9.5006) -> (-16.2979, 8.7114)
  line L54 (-16.2979, 8.7114) -> (-16.7057, 7.9012)
  line L55 (-16.7057, 7.9012) -> (-17.0733, 7.072)
  line L56 (-17.0733, 7.072) -> (-17.3997, 6.2257)
  line L57 (-17.3997, 6.2257) -> (-17.6843, 5.3645)
  line L58 (-17.6843, 5.3645) -> (-17.9262, 4.4903)
  line L59 (-17.9262, 4.4903) -> (-18.1249, 3.6053)
  line L60 (-18.1249, 3.6053) -> (-18.28, 2.7116)
  line L61 (-18.28, 2.7116) -> (-18.391, 1.8114)
  line L62 (-18.391, 1.8114) -> (-18.4577, 0.9068)
  line L63 (-18.4577, 0.9068) -> (-18.48, 0)
  line L64 (-18.48, 0) -> (-18.4577, -0.9068)
  line L65 (-18.4577, -0.9068) -> (-18.391, -1.8114)
  line L66 (-18.391, -1.8114) -> (-18.28, -2.7116)
  line L67 (-18.28, -2.7116) -> (-18.1249, -3.6053)
  line L68 (-18.1249, -3.6053) -> (-17.9262, -4.4903)
  line L69 (-17.9262, -4.4903) -> (-17.6843, -5.3645)
  line L70 (-17.6843, -5.3645) -> (-17.3997, -6.2257)
  line L71 (-17.3997, -6.2257) -> (-17.0733, -7.072)
  line L72 (-17.0733, -7.072) -> (-16.7057, -7.9012)
  line L73 (-16.7057, -7.9012) -> (-16.2979, -8.7114)
  line L74 (-16.2979, -8.7114) -> (-15.8508, -9.5006)
  line L75 (-15.8508, -9.5006) -> (-15.3656, -10.2669)
  line L76 (-15.3656, -10.2669) -> (-14.8433, -11.0085)
  line L77 (-14.8433, -11.0085) -> (-14.2852, -11.7236)
  line L78 (-14.2852, -11.7236) -> (-13.6928, -12.4104)
  line L79 (-13.6928, -12.4104) -> (-13.0673, -13.0673)
  line L80 (-13.0673, -13.0673) -> (-12.4104, -13.6928)
  line L81 (-12.4104, -13.6928) -> (-11.7236, -14.2852)
  line L82 (-11.7236, -14.2852) -> (-11.0085, -14.8433)
  line L83 (-11.0085, -14.8433) -> (-10.2669, -15.3656)
  line L84 (-10.2669, -15.3656) -> (-9.5006, -15.8508)
  line L85 (-9.5006, -15.8508) -> (-8.7114, -16.2979)
  line L86 (-8.7114, -16.2979) -> (-7.9012, -16.7057)
  line L87 (-7.9012, -16.7057) -> (-7.072, -17.0733)
  line L88 (-7.072, -17.0733) -> (-6.2257, -17.3997)
  line L89 (-6.2257, -17.3997) -> (-5.3645, -17.6843)
  line L90 (-5.3645, -17.6843) -> (-4.4903, -17.9262)
  line L91 (-4.4903, -17.9262) -> (-3.6053, -18.1249)
  line L92 (-3.6053, -18.1249) -> (-2.7116, -18.28)
  line L93 (-2.7116, -18.28) -> (-1.8114, -18.391)
  line L94 (-1.8114, -18.391) -> (-0.9068, -18.4577)
  line L95 (-0.9068, -18.4577) -> (0, -18.48)
  line L96 (0, -18.48) -> (0.9068, -18.4577)
  line L97 (0.9068, -18.4577) -> (1.8114, -18.391)
  line L98 (1.8114, -18.391) -> (2.7116, -18.28)
  line L99 (2.7116, -18.28) -> (3.6053, -18.1249)
  line L100 (3.6053, -18.1249) -> (4.4903, -17.9262)
  line L101 (4.4903, -17.9262) -> (5.3645, -17.6843)
  line L102 (5.3645, -17.6843) -> (6.2257, -17.3997)
  line L103 (6.2257, -17.3997) -> (7.072, -17.0733)
  line L104 (7.072, -17.0733) -> (7.9012, -16.7057)
  line L105 (7.9012, -16.7057) -> (8.7114, -16.2979)
  line L106 (8.7114, -16.2979) -> (9.5006, -15.8508)
  line L107 (9.5006, -15.8508) -> (10.2669, -15.3656)
  line L108 (10.2669, -15.3656) -> (11.0085, -14.8433)
  line L109 (11.0085, -14.8433) -> (11.7236, -14.2852)
  line L110 (11.7236, -14.2852) -> (12.4104, -13.6928)
  line L111 (12.4104, -13.6928) -> (13.0673, -13.0673)
  line L112 (13.0673, -13.0673) -> (13.6928, -12.4104)
  line L113 (13.6928, -12.4104) -> (14.2852, -11.7236)
  line L114 (14.2852, -11.7236) -> (14.8433, -11.0085)
  line L115 (14.8433, -11.0085) -> (15.3656, -10.2669)
  line L116 (15.3656, -10.2669) -> (15.8508, -9.5006)
  line L117 (15.8508, -9.5006) -> (16.2979, -8.7114)
  line L118 (16.2979, -8.7114) -> (16.7057, -7.9012)
  line L119 (16.7057, -7.9012) -> (17.0733, -7.072)
  line L120 (17.0733, -7.072) -> (17.3997, -6.2257)
  line L121 (17.3997, -6.2257) -> (17.6843, -5.3645)
  line L122 (17.6843, -5.3645) -> (17.9262, -4.4903)
  line L123 (17.9262, -4.4903) -> (18.1249, -3.6053)
  line L124 (18.1249, -3.6053) -> (18.28, -2.7116)
  line L125 (18.28, -2.7116) -> (18.391, -1.8114)
  line L126 (18.391, -1.8114) -> (18.4577, -0.9068)
  line L127 (18.4577, -0.9068) -> (18.48, 0)
  line L128 (17.6088, -0.8651) -> (17.5451, -1.728)
  line L129 (17.5451, -1.728) -> (17.4392, -2.5869)
  line L130 (17.4392, -2.5869) -> (17.2912, -3.4394)
  line L131 (17.2912, -3.4394) -> (17.1017, -4.2837)
  line L132 (17.1017, -4.2837) -> (16.8709, -5.1177)
  line L133 (16.8709, -5.1177) -> (16.5994, -5.9394)
  line L134 (16.5994, -5.9394) -> (16.288, -6.7467)
  line L135 (16.288, -6.7467) -> (15.9373, -7.5378)
  line L136 (15.9373, -7.5378) -> (15.5483, -8.3107)
  line L137 (15.5483, -8.3107) -> (15.1218, -9.0636)
  line L138 (15.1218, -9.0636) -> (14.6588, -9.7947)
  line L139 (14.6588, -9.7947) -> (14.1605, -10.5022)
  line L140 (14.1605, -10.5022) -> (13.6282, -11.1844)
  line L141 (13.6282, -11.1844) -> (13.063, -11.8396)
  line L142 (13.063, -11.8396) -> (12.4663, -12.4663)
  line L143 (12.4663, -12.4663) -> (11.8396, -13.063)
  line L144 (11.8396, -13.063) -> (11.1844, -13.6282)
  line L145 (11.1844, -13.6282) -> (10.5022, -14.1605)
  line L146 (10.5022, -14.1605) -> (9.7947, -14.6588)
  line L147 (9.7947, -14.6588) -> (9.0636, -15.1218)
  line L148 (9.0636, -15.1218) -> (8.3107, -15.5483)
  line L149 (8.3107, -15.5483) -> (7.5378, -15.9373)
  line L150 (7.5378, -15.9373) -> (6.7467, -16.288)
  line L151 (6.7467, -16.288) -> (5.9394, -16.5994)
  line L152 (5.9394, -16.5994) -> (5.1177, -16.8709)
  line L153 (5.1177, -16.8709) -> (4.2837, -17.1017)
  line L154 (4.2837, -17.1017) -> (3.4394, -17.2912)
  line L155 (3.4394, -17.2912) -> (2.5869, -17.4392)
  line L156 (2.5869, -17.4392) -> (1.728, -17.5451)
  line L157 (1.728, -17.5451) -> (0.8651, -17.6088)
  line L158 (0.8651, -17.6088) -> (0, -17.63)
  line L159 (0, -17.63) -> (-0.8651, -17.6088)
  line L160 (-0.8651, -17.6088) -> (-1.728, -17.5451)
  line L161 (-1.728, -17.5451) -> (-2.5869, -17.4392)
  line L162 (-2.5869, -17.4392) -> (-3.4394, -17.2912)
  line L163 (-3.4394, -17.2912) -> (-4.2837, -17.1017)
  line L164 (-4.2837, -17.1017) -> (-5.1177, -16.8709)
  line L165 (-5.1177, -16.8709) -> (-5.9394, -16.5994)
  line L166 (-5.9394, -16.5994) -> (-6.7467, -16.288)
  line L167 (-6.7467, -16.288) -> (-7.5378, -15.9373)
  line L168 (-7.5378, -15.9373) -> (-8.3107, -15.5483)
  line L169 (-8.3107, -15.5483) -> (-9.0636, -15.1218)
  line L170 (-9.0636, -15.1218) -> (-9.7947, -14.6588)
  line L171 (-9.7947, -14.6588) -> (-10.5022, -14.1605)
  line L172 (-10.5022, -14.1605) -> (-11.1844, -13.6282)
  line L173 (-11.1844, -13.6282) -> (-11.8396, -13.063)
  line L174 (-11.8396, -13.063) -> (-12.4663, -12.4663)
  line L175 (-12.4663, -12.4663) -> (-13.063, -11.8396)
  line L176 (-13.063, -11.8396) -> (-13.6282, -11.1844)
  line L177 (-13.6282, -11.1844) -> (-14.1605, -10.5022)
  line L178 (-14.1605, -10.5022) -> (-14.6588, -9.7947)
  line L179 (-14.6588, -9.7947) -> (-15.1218, -9.0636)
  line L180 (-15.1218, -9.0636) -> (-15.5483, -8.3107)
  line L181 (-15.5483, -8.3107) -> (-15.9373, -7.5378)
  line L182 (-15.9373, -7.5378) -> (-16.288, -6.7467)
  line L183 (-16.288, -6.7467) -> (-16.5994, -5.9394)
  line L184 (-16.5994, -5.9394) -> (-16.8709, -5.1177)
  line L185 (-16.8709, -5.1177) -> (-17.1017, -4.2837)
  line L186 (-17.1017, -4.2837) -> (-17.2912, -3.4394)
  line L187 (-17.2912, -3.4394) -> (-17.4392, -2.5869)
  line L188 (-17.4392, -2.5869) -> (-17.5451, -1.728)
  line L189 (-17.5451, -1.728) -> (-17.6088, -0.8651)
  line L190 (-17.6088, -0.8651) -> (-17.63, 0)
  line L191 (-17.63, 0) -> (-17.6088, 0.8651)
  line L192 (-17.6088, 0.8651) -> (-17.5451, 1.728)
  line L193 (-17.5451, 1.728) -> (-17.4392, 2.5869)
  line L194 (-17.4392, 2.5869) -> (-17.2912, 3.4394)
  line L195 (-17.2912, 3.4394) -> (-17.1017, 4.2837)
  line L196 (-17.1017, 4.2837) -> (-16.8709, 5.1177)
  line L197 (-16.8709, 5.1177) -> (-16.5994, 5.9394)
  line L198 (-16.5994, 5.9394) -> (-16.288, 6.7467)
  line L199 (-16.288, 6.7467) -> (-15.9373, 7.5378)
  line L200 (-15.9373, 7.5378) -> (-15.5483, 8.3107)
  line L201 (-15.5483, 8.3107) -> (-15.1218, 9.0636)
  line L202 (-15.1218, 9.0636) -> (-14.6588, 9.7947)
  line L203 (-14.6588, 9.7947) -> (-14.1605, 10.5022)
  line L204 (-14.1605, 10.5022) -> (-13.6282, 11.1844)
  line L205 (-13.6282, 11.1844) -> (-13.063, 11.8396)
  line L206 (-13.063, 11.8396) -> (-12.4663, 12.4663)
  line L207 (-12.4663, 12.4663) -> (-11.8396, 13.063)
  line L208 (-11.8396, 13.063) -> (-11.1844, 13.6282)
  line L209 (-11.1844, 13.6282) -> (-10.5022, 14.1605)
  line L210 (-10.5022, 14.1605) -> (-9.7947, 14.6588)
  line L211 (-9.7947, 14.6588) -> (-9.0636, 15.1218)
  line L212 (-9.0636, 15.1218) -> (-8.3107, 15.5483)
  line L213 (-8.3107, 15.5483) -> (-7.5378, 15.9373)
  line L214 (-7.5378, 15.9373) -> (-6.7467, 16.288)
  line L215 (-6.7467, 16.288) -> (-5.9394, 16.5994)
  line L216 (-5.9394, 16.5994) -> (-5.1177, 16.8709)
  line L217 (-5.1177, 16.8709) -> (-4.2837, 17.1017)
  line L218 (-4.2837, 17.1017) -> (-3.4394, 17.2912)
  line L219 (-3.4394, 17.2912) -> (-2.5869, 17.4392)
  line L220 (-2.5869, 17.4392) -> (-1.728, 17.5451)
  line L221 (-1.728, 17.5451) -> (-0.8651, 17.6088)
  line L222 (-0.8651, 17.6088) -> (0, 17.63)
  line L223 (0, 17.63) -> (0.8651, 17.6088)
  line L224 (0.8651, 17.6088) -> (1.728, 17.5451)
  line L225 (1.728, 17.5451) -> (2.5869, 17.4392)
  line L226 (2.5869, 17.4392) -> (3.4394, 17.2912)
  line L227 (3.4394, 17.2912) -> (4.2837, 17.1017)
  line L228 (4.2837, 17.1017) -> (5.1177, 16.8709)
  line L229 (5.1177, 16.8709) -> (5.9394, 16.5994)
  line L230 (5.9394, 16.5994) -> (6.7467, 16.288)
  line L231 (6.7467, 16.288) -> (7.5378, 15.9373)
  line L232 (7.5378, 15.9373) -> (8.3107, 15.5483)
  line L233 (8.3107, 15.5483) -> (9.0636, 15.1218)
  line L234 (9.0636, 15.1218) -> (9.7947, 14.6588)
  line L235 (9.7947, 14.6588) -> (10.5022, 14.1605)
  line L236 (10.5022, 14.1605) -> (11.1844, 13.6282)
  line L237 (11.1844, 13.6282) -> (11.8396, 13.063)
  line L238 (11.8396, 13.063) -> (12.4663, 12.4663)
  line L239 (12.4663, 12.4663) -> (13.063, 11.8396)
  line L240 (13.063, 11.8396) -> (13.6282, 11.1844)
  line L241 (13.6282, 11.1844) -> (14.1605, 10.5022)
  line L242 (14.1605, 10.5022) -> (14.6588, 9.7947)
  line L243 (14.6588, 9.7947) -> (15.1218, 9.0636)
  line L244 (15.1218, 9.0636) -> (15.5483, 8.3107)
  line L245 (15.5483, 8.3107) -> (15.9373, 7.5378)
  line L246 (15.9373, 7.5378) -> (16.288, 6.7467)
  line L247 (16.288, 6.7467) -> (16.5994, 5.9394)
  line L248 (16.5994, 5.9394) -> (16.8709, 5.1177)
  line L249 (16.8709, 5.1177) -> (17.1017, 4.2837)
  line L250 (17.1017, 4.2837) -> (17.2912, 3.4394)
  line L251 (17.2912, 3.4394) -> (17.4392, 2.5869)
  line L252 (17.4392, 2.5869) -> (17.5451, 1.728)
  line L253 (17.5451, 1.728) -> (17.6088, 0.8651)
  line L254 (17.6088, 0.8651) -> (17.63, 0)
  line L255 (17.63, 0) -> (17.6088, -0.8651)
extrude "中环_002 (1)" add sketch "草图3" along normal blind 1.23 bodies 1 in component "01_月饼_金_68mm"